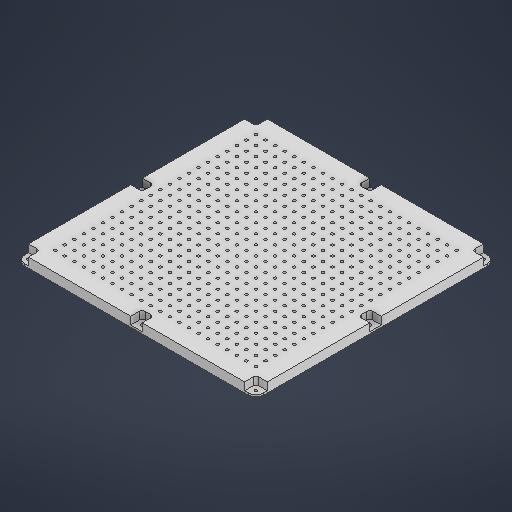
# Autodesk Inventor part: Upperpart
Saved by Autodesk Inventor 2027.2 (Build 312334000, 334)
## iProperties
Created: 2026-11-18
Part Number: Upperpart
Material: Generic
Document SubType Name: Modeling
Designer: Brian Wang
Density: 1 g/cm^3
Appearance: Default
Author: Brian Wang
Autodesk Inventor part; units mm, degrees
ref_plane "YZ Plane" through (0, 0, 0) normal (1, 0, 0) x (0, 1, 0)
ref_plane "XZ Plane" through (0, 0, 0) normal (0, 1, 0) x (-1, 0, 0)
ref_plane "XY Plane" through (0, 0, 0) normal (0, 0, 1) x (1, 0, 0)
sketch "Sketch1" plane through (0, 0, 0) normal (0, 1, 0) x (-1, 0, 0)
  line L0 (121.9275, 120.2099) -> (-128.0725, 120.2099)
  line L1 (-128.0725, 120.2099) -> (-128.0725, -129.7901)
  line L2 (-128.0725, -129.7901) -> (121.9275, -129.7901)
  line L3 (121.9275, -129.7901) -> (121.9275, 120.2099)
  point P0 (0, 0)
  dimension "d0" = 250
  dimension "d1" = 250
  constraints: 8 end point, 2 parallel, 1 horizontal, 1 perpendicular
  measures "d0" distance of L2.end L1.end
  measures "d1" distance of L1.end L0.end
extrude "Extrusion1" add sketch "Sketch1" along normal blind 10
fillet "Fillet1" radius 8 4 edges at (-121.9275, 5, 120.2099) (128.0725, 5, 120.2099) (128.0725, 5, -129.7901) (-121.9275, 5, -129.7901)
sketch "Sketch2" plane through (0, 10, 0) normal (0, 1, 0) x (1, 0, 0)
  arc A0 (-113.9275, 129.7901) -> (-121.9275, 121.7901) centre (-113.9275, 121.7901) ccw projected
  circle A1 centre (122.0725, 123.7901) radius 1.5
  circle A2 centre (122.0725, -114.2099) radius 1.5
  circle A3 centre (-115.9275, -114.2099) radius 1.5
  line L0 (120.0725, 129.7901) -> (-113.9275, 129.7901) projected
  circle A4 centre (-115.9275, 123.7901) radius 1.5
  line L1 (-121.9275, 121.7901) -> (-121.9275, -112.2099) projected
  line L2 (128.0725, -112.2099) -> (128.0725, 121.7901) projected
  line L3 (-113.9275, -120.2099) -> (120.0725, -120.2099) projected
  point P0 (0, 0)
  dimension "d6" = 3
  dimension "d7" = 3
  dimension "d8" = 3
  dimension "d10" = 3
  dimension "d11" = 6
  dimension "d12" = 6
  dimension "d13" = 6
  dimension "d14" = 6
  dimension "d15" = 6
  dimension "d16" = 6
  dimension "d17" = 6
  dimension "d18" = 6
  constraints: 4 centre point
  measures "d6" diameter of A1
  measures "d7" diameter of A2
  measures "d8" diameter of A3
  measures "d10" diameter of A4
  measures "d11" distance from line of L0 A4.centre
  measures "d12" distance from line of L1 A4.centre
  measures "d13" distance from line of L0 A1.centre
  measures "d14" distance from line of L2 A1.centre
  measures "d15" distance from line of L1 A3.centre
  measures "d16" distance from line of L3 A3.centre
  measures "d17" distance from line of L2 A2.centre
  measures "d18" distance from line of L3 A2.centre
extrude "Extrusion2" cut sketch "Sketch2" against normal blind 234
sketch "Sketch3" plane through (0, 10, 0) normal (0, 1, 0) x (1, 0, 0)
  circle A0 centre (-115.9275, 4.7901) radius 1.5
  circle A1 centre (122.0725, 4.7901) radius 1.5
  circle A2 centre (3.0725, 123.7901) radius 1.5
  circle A3 centre (3.0725, -114.2099) radius 1.5
  circle A4 centre (-115.9275, 123.7901) radius 1.5 projected
  circle A5 centre (122.0725, 123.7901) radius 1.5 projected
  circle A6 centre (122.0725, -114.2099) radius 1.5 projected
  point P0 (0, 0)
  dimension "d21" = 3
  dimension "d22" = 3
  dimension "d23" = 3
  dimension "d24" = 3
  dimension "d25" = 119
  dimension "d26" = 119
  dimension "d27" = 119
  dimension "d28" = 119
  constraints: 4 centre point
  measures "d21" diameter of A0
  measures "d22" diameter of A1
  measures "d23" diameter of A2
  measures "d24" diameter of A3
  measures "d25" distance of A4.centre A2.centre
  measures "d26" distance of A4.centre A0.centre
  measures "d27" distance of A5.centre A1.centre
  measures "d28" distance of A6.centre A3.centre
extrude "Extrusion3" cut sketch "Sketch3" against normal blind 234 contours A0 | A1 | A2 | A3
sketch "Sketch4" plane through (0, 10, 0) normal (0, 1, 0) x (1, 0, 0)
  line L0 (-121.9275, 121.7901) -> (-121.9275, -112.2099) projected
  line L1 (-121.9275, 10.7901) -> (-109.9275, 10.7901)
  line L2 (-109.9275, 10.7901) -> (-109.9275, -1.2099)
  line L3 (-109.9275, -1.2099) -> (-121.9275, -1.2099)
  line L4 (-121.9275, -1.2099) -> (-121.9275, 10.7901)
  circle A0 centre (-115.9275, 4.7901) radius 1.5 projected
  line L5 (-121.9275, 129.7901) -> (-109.9275, 129.7901)
  line L6 (-109.9275, 129.7901) -> (-109.9275, 117.7901)
  line L7 (-109.9275, 117.7901) -> (-121.9275, 117.7901)
  line L8 (-121.9275, 117.7901) -> (-121.9275, 129.7901)
  line L9 (-2.9275, 129.7901) -> (9.0725, 129.7901)
  line L10 (9.0725, 129.7901) -> (9.0725, 117.7901)
  line L11 (9.0725, 117.7901) -> (-2.9275, 117.7901)
  line L12 (-2.9275, 117.7901) -> (-2.9275, 129.7901)
  circle A1 centre (3.0725, 123.7901) radius 1.5 projected
  line L13 (128.0725, 129.7901) -> (116.0725, 129.7901)
  line L14 (116.0725, 129.7901) -> (116.0725, 117.7901)
  line L15 (116.0725, 117.7901) -> (128.0725, 117.7901)
  line L16 (128.0725, 117.7901) -> (128.0725, 129.7901)
  line L17 (128.0725, 10.7901) -> (116.0725, 10.7901)
  line L18 (116.0725, 10.7901) -> (116.0725, -1.2099)
  line L19 (116.0725, -1.2099) -> (128.0725, -1.2099)
  line L20 (128.0725, -1.2099) -> (128.0725, 10.7901)
  circle A2 centre (122.0725, 4.7901) radius 1.5 projected
  line L21 (128.0725, -120.2099) -> (116.0725, -120.2099)
  line L22 (116.0725, -120.2099) -> (116.0725, -108.2099)
  line L23 (116.0725, -108.2099) -> (128.0725, -108.2099)
  line L24 (128.0725, -108.2099) -> (128.0725, -120.2099)
  line L25 (-2.9275, -120.2099) -> (9.0725, -120.2099)
  line L26 (9.0725, -120.2099) -> (9.0725, -108.2099)
  line L27 (9.0725, -108.2099) -> (-2.9275, -108.2099)
  line L28 (-2.9275, -108.2099) -> (-2.9275, -120.2099)
  circle A3 centre (3.0725, -114.2099) radius 1.5 projected
  line L29 (-121.9275, -120.2099) -> (-109.9275, -120.2099)
  line L30 (-109.9275, -120.2099) -> (-109.9275, -108.2099)
  line L31 (-109.9275, -108.2099) -> (-121.9275, -108.2099)
  line L32 (-121.9275, -108.2099) -> (-121.9275, -120.2099)
  point P0 (0, 0)
  point P1 (9.0725, 123.7901)
  dimension "d31" = 12
  dimension "d32" = 12
  dimension "d33" = 6
  dimension "d34" = 12
  dimension "d35" = 12
  dimension "d36" = 12
  dimension "d37" = 12
  dimension "d38" = 6
  dimension "d39" = 12
  dimension "d40" = 12
  dimension "d41" = 12
  dimension "d42" = 12
  dimension "d43" = 6
  dimension "d44" = 12
  dimension "d45" = 12
  dimension "d46" = 12
  dimension "d47" = 12
  dimension "d48" = 6
  dimension "d49" = 12
  dimension "d50" = 12
  constraints: 64 end point, 16 parallel, 8 horizontal, 8 perpendicular, 4 point on line, 1 midpoint
  measures "d31" distance of L2.end L3.end
  measures "d32" distance of L1.end L2.end
  measures "d33" distance from line of L1 A0.centre
  measures "d34" distance of L6.end L7.end
  measures "d35" distance of L5.end L6.end
  measures "d36" distance of L10.end L11.end
  measures "d37" distance of L9.end L10.end
  measures "d38" distance of point (9.072, 123.79) A1.centre
  measures "d39" distance of L15.end L14.end
  measures "d40" distance of L14.end L13.end
  measures "d41" distance of L19.end L18.end
  measures "d42" distance of L18.end L17.end
  measures "d43" distance from line of L17 A2.centre
  measures "d44" distance of L22.end L23.end
  measures "d45" distance of L21.end L22.end
  measures "d46" distance of L27.end L26.end
  measures "d47" distance of L26.end L25.end
  measures "d48" distance from line of L26 A3.centre
  measures "d49" distance of L31.end L30.end
  measures "d50" distance of L30.end L29.end
extrude "Extrusion4" cut sketch "Sketch4" against normal blind 8
fillet "Face Fillet1" radius 3 1 edges at (-2.9275, 6, 108.2099)
fillet "Face Fillet2" radius 3 1 edges at (9.0725, 6, 108.2099)
fillet "Face Fillet3" radius 3 1 edges at (-109.9275, 6, 108.2099)
fillet "Face Fillet4" radius 3 1 edges at (-109.9275, 6, -10.7901)
fillet "Face Fillet5" radius 3 1 edges at (-109.9275, 6, 1.2099)
fillet "Face Fillet6" radius 3 1 edges at (-109.9275, 6, -117.7901)
fillet "Face Fillet7" radius 3 1 edges at (9.0725, 6, -117.7901)
fillet "Face Fillet8" radius 3 1 edges at (-2.9275, 6, -117.7901)
fillet "Face Fillet9" radius 3 1 edges at (116.0725, 6, -117.7901)
fillet "Face Fillet10" radius 3 1 edges at (116.0725, 6, 1.2099)
fillet "Face Fillet11" radius 3 1 edges at (116.0725, 6, -10.7901)
fillet "Face Fillet12" radius 3 1 edges at (116.0725, 6, 108.2099)
sketch "Sketch5" plane through (0, 10, 0) normal (0, 1, 0) x (1, 0, 0)
  line L0 (-106.9275, 114.7901) -> (113.0725, 114.7901)
  line L1 (113.0725, 114.7901) -> (113.0725, -105.2099)
  line L2 (113.0725, -105.2099) -> (-106.9275, -105.2099)
  line L3 (-106.9275, -105.2099) -> (-106.9275, 114.7901)
  line L4 (-121.9275, 117.7901) -> (-121.9275, 10.7901) projected
  line L5 (116.0725, 129.7901) -> (9.0725, 129.7901) projected
  circle A0 centre (-101.9275, 109.7901) radius 1.45
  point P0 (0, 0)
  dimension "d65" = 220
  dimension "d66" = 220
  dimension "d67" = 15
  dimension "d68" = 15
  dimension "d69" = 2.9
  dimension "d70" = 5
  dimension "d71" = 5
  constraints: 8 end point, 2 parallel, 1 centre point, 1 horizontal, 1 perpendicular
  measures "d65" distance of L2.end L0.start
  measures "d66" distance of L0.start L0.end
  measures "d67" distance between parallel lines of L4 L3
  measures "d68" distance between parallel lines of L5 L0
  measures "d69" diameter of A0
  measures "d70" distance from line of L0 A0.centre
  measures "d71" distance from line of L3 A0.centre
extrude "Extrusion5" cut sketch "Sketch5" against normal through all contours A0
pattern_linear "Rectangular Pattern1" count 22 spacing 10 along (0, 0, 1) count 22 spacing 10 along (1, 0, 0) of "Extrusion5"
body "Solid1"
